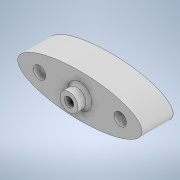
# Autodesk Inventor part: baza_arc_6mm
Saved by Autodesk Inventor 2020 (Build 240168000, 168)
## iProperties
Created: 2023-04-30
Part Number: baza_arc_6mm
Material: Generic
Document SubType Name: Modeling
Designer: user
Density: 1 g/cm^3
Appearance: Default
Author: user
Autodesk Inventor part; units mm, degrees
ref_plane "YZ Plane" through (0, 0, 0) normal (1, 0, 0) x (0, 1, 0)
ref_plane "XZ Plane" through (0, 0, 0) normal (0, 1, 0) x (-1, 0, 0)
ref_plane "XY Plane" through (0, 0, 0) normal (0, 0, 1) x (1, 0, 0)
sketch "Sketch1" plane through (0, 0, 0) normal (0, 0, 1) x (1, 0, 0)
  circle A0 centre (0, 0) radius 1.5
  circle A1 centre (0, 0) radius 2.9
  dimension "d12" = 5.8
  dimension "d17" = 3
  dimension "d18" = 1.4
  constraints: 2 centre point, 2 coincident
  measures "d12" diameter of A1
  measures "d17" diameter of A0
  measures "d18" radial gap between concentric circles of A1 A0
extrude "Extrusion1" add sketch "Sketch1" along normal blind 3.5
sketch "Sketch2" plane through (0, 0, 0) normal (0, 0, -1) x (-1, 0, 0)
  ellipse E0 centre (0, 0) end of major axis (20, 0) minor radius 6.9
  circle A0 centre (13, 0) radius 2
  line L0 (0, -12.8793) -> (0, 14.0619) construction
  circle A1 centre (-13, 0) radius 2
  circle A2 centre (0, 0) radius 2.4
  circle A3 centre (0, 0) radius 1.5 projected
  circle A4 centre (0, 0) radius 3.9
  point P0 (20, 0)
  dimension "d6" = 7
  dimension "d8" = 4
  constraints: 4 centre point, 3 coincident, 2 end point, 1 horizontal alignment, 1 symmetric about line, 1 vertical, 3 other
  measures "d6" distance of point (13, 0) point (20, 0)
  measures "d8" diameter of A0
extrude "Extrusion3" add sketch "Sketch2" along normal blind 10 contours E0 | A4
fillet "Fillet2" radius 1 1 edges at (-2.9, 0, 0)
body "Solid1"
